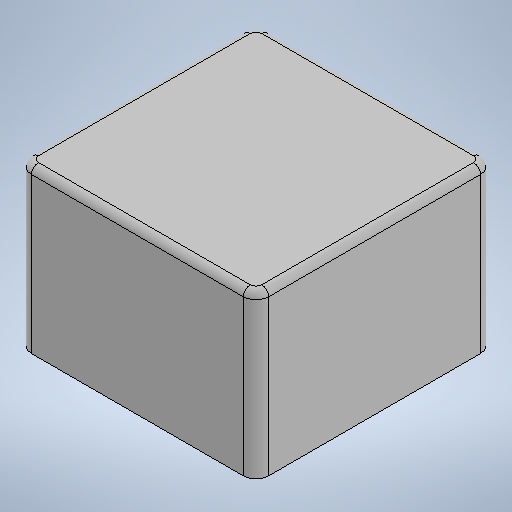
# Autodesk Inventor part: FEXL0430A
Saved by Autodesk Inventor 2025.2 (Build 292293000, 293)
## iProperties
Created: 2025-06-22
Part Number: FEXL0430A
Material: Generic
Document SubType Name: Modeling
Designer: K. Paulsen
Density: 1 g/cm^3
Appearance: Default
Author: K. Paulsen
Autodesk Inventor part; units mm, degrees
ref_plane "YZ Plane" through (0, 0, 0) normal (1, 0, 0) x (0, 1, 0)
ref_plane "XZ Plane" through (0, 0, 0) normal (0, 1, 0) x (-1, 0, 0)
ref_plane "XY Plane" through (0, 0, 0) normal (0, 0, 1) x (1, 0, 0)
sketch "Sketch1" plane through (0, 0, 0) normal (0, 1, 0) x (-1, 0, 0)
  line L0 (0, 0) -> (1.29, 0) construction
  line L1 (1.51, -1.7) -> (1.07, -1.7)
  line L2 (0.85, -1.48) -> (0.85, 1.48)
  line L3 (1.07, 1.7) -> (1.51, 1.7)
  line L4 (1.73, 1.48) -> (1.73, -1.48)
  line L5 (1.73, -1.7) -> (0.85, 1.7) construction
  line L6 (0.85, -1.7) -> (1.73, 1.7) construction
  arc A0 (1.07, 1.7) -> (0.85, 1.48) centre (1.07, 1.48) ccw
  arc A1 (1.73, 1.48) -> (1.51, 1.7) centre (1.51, 1.48) ccw
  arc A2 (1.51, -1.7) -> (1.73, -1.48) centre (1.51, -1.48) ccw
  arc A3 (0.85, -1.48) -> (1.07, -1.7) centre (1.07, -1.48) ccw
  line L7 (-1.83, -2.05) -> (1.83, -2.05) construction
  line L8 (2.05, -1.83) -> (2.05, 1.83) construction
  line L9 (1.83, 2.05) -> (-1.83, 2.05) construction
  line L10 (-2.05, 1.83) -> (-2.05, -1.83) construction
  line L11 (-2.05, -2.05) -> (2.05, 2.05) construction
  line L12 (2.05, -2.05) -> (-2.05, 2.05) construction
  arc A4 (2.05, 1.83) -> (1.83, 2.05) centre (1.83, 1.83) ccw construction
  arc A5 (1.83, -2.05) -> (2.05, -1.83) centre (1.83, -1.83) ccw construction
  arc A6 (-2.05, -1.83) -> (-1.83, -2.05) centre (-1.83, -1.83) ccw construction
  arc A7 (-1.83, 2.05) -> (-2.05, 1.83) centre (-1.83, 1.83) ccw construction
  line L13 (0, 0) -> (0, 2.05) construction
  line L14 (-1.51, -1.7) -> (-1.07, -1.7)
  line L15 (-0.85, -1.48) -> (-0.85, 1.48)
  line L16 (-1.07, 1.7) -> (-1.51, 1.7)
  line L17 (-1.73, 1.48) -> (-1.73, -1.48)
  line L18 (-1.73, -1.7) -> (-0.85, 1.7) construction
  line L19 (-0.85, -1.7) -> (-1.73, 1.7) construction
  arc A8 (-0.85, 1.48) -> (-1.07, 1.7) centre (-1.07, 1.48) ccw
  arc A9 (-1.51, 1.7) -> (-1.73, 1.48) centre (-1.51, 1.48) ccw
  arc A10 (-1.73, -1.48) -> (-1.51, -1.7) centre (-1.51, -1.48) ccw
  arc A11 (-1.07, -1.7) -> (-0.85, -1.48) centre (-1.07, -1.48) ccw
  point P0 (-1.29, 0)
  dimension "d0" = 0.22
  dimension "d1" = 3.4
  dimension "d2" = 0.88
  dimension "d3" = 4.1
  dimension "d4" = 4.1
  dimension "d5" = 0.22
  dimension "d6" = 1.7
  constraints: 40 end point, 24 point on circle, 24 point on line, 17 symmetric about line, 16 tangent, 12 centre point, 6 equal radius, 5 midpoint, 4 parallel, 3 horizontal, 2 perpendicular, 4 other
  measures "d0" radius of A0
  measures "d1" distance between parallel lines of L1 L3
  measures "d2" distance between parallel lines of L4 L2
  measures "d3" distance of L12.end L11.end
  measures "d4" distance of L11.end L12.start
  measures "d5" radius of A4
  measures "d6" distance between parallel lines of L2 L15
extrude "Extrusion1" add sketch "Sketch1" along normal blind 0.1
sketch "Sketch2" plane through (0, 0.1, 0) normal (0, 1, 0) x (1, 0, 0)
  line L0 (-1.83, -2.05) -> (1.83, -2.05) projected
  arc A0 (-2.05, -1.83) -> (-1.83, -2.05) centre (-1.83, -1.83) ccw projected
  line L1 (-2.05, 1.83) -> (-2.05, -1.83) projected
  arc A1 (-1.83, 2.05) -> (-2.05, 1.83) centre (-1.83, 1.83) ccw projected
  line L2 (1.83, 2.05) -> (-1.83, 2.05) projected
  arc A2 (2.05, 1.83) -> (1.83, 2.05) centre (1.83, 1.83) ccw projected
  line L3 (2.05, -1.83) -> (2.05, 1.83) projected
  arc A3 (1.83, -2.05) -> (2.05, -1.83) centre (1.83, -1.83) ccw projected
  point P0 (0, 0)
extrude "Extrusion2" add sketch "Sketch2" along normal blind 2.8
fillet "Fillet1" radius 0.12 8 edges at (1.9856, 2.9, 1.9856) (2.05, 2.9, 0) (1.9856, 2.9, -1.9856) (0, 2.9, -2.05) (-1.9856, 2.9, -1.9856) (-2.05, 2.9, 0) (-1.9856, 2.9, 1.9856) (0, 2.9, 2.05)
body "Solid1"
